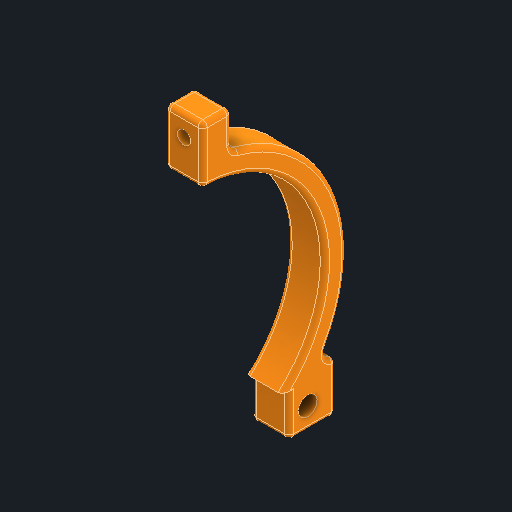
# Autodesk Inventor part: ra_wrap_strap_mz
Saved by Autodesk Inventor 2027.1 (Build 311270010, 270A)
## iProperties
Created: 2026-11-04
Part Number: ra_wrap_strap_mz
Material: Generic
Description: RA wrap strap -Z half: wraps over the RA body, lug on the flat bit -Z axial M5 (M5x25), M4x20 top joint into an M4 nut; print PETG/ASA
Document SubType Name: Modeling
Designer: Claude (from photos)
Density: 1 g/cm^3
Appearance: Orange
Mass: 11.5728 g
Surface Area: 53.282 cm^2
Volume: 11.5728 cm^3
Author: alexg
Autodesk Inventor part; units mm, degrees
ref_plane "Work Plane1" through (1, 0, 0) normal (1, 0, 0) x (0, 1, 0)
sketch "Band sketch" plane through (1, 0, 0) normal (1, 0, 0) x (0, 1, 0)
  circle A0 centre (0, 0) radius 47
  constraints: 1 centre point
extrude "Band" add sketch "Band sketch" along normal blind 12
ref_plane "Work Plane2" through (1, 0, 0) normal (1, 0, 0) x (0, 1, 0)
sketch "Keep this half sketch" plane through (1, 0, 0) normal (1, 0, 0) x (0, 1, 0)
  line L0 (-60, -0.75) -> (60, -0.75)
  line L1 (60, -0.75) -> (60, 60)
  line L2 (60, 60) -> (-60, 60)
  line L3 (-60, 60) -> (-60, -0.75)
  constraints: 8 end point, 2 parallel, 1 horizontal, 1 perpendicular
extrude "Keep this half" cut sketch "Keep this half sketch" along normal blind 12
ref_plane "Work Plane3" through (1, 0, 0) normal (1, 0, 0) x (0, 1, 0)
sketch "Open below the RA body (latitude pivot web) sketch" plane through (1, 0, 0) normal (1, 0, 0) x (0, 1, 0)
  line L0 (-60, -60) -> (-30, -60)
  line L1 (-30, -60) -> (-30, 60)
  line L2 (-30, 60) -> (-60, 60)
  line L3 (-60, 60) -> (-60, -60)
  constraints: 8 end point, 2 parallel, 1 horizontal, 1 perpendicular
extrude "Open below the RA body (latitude pivot web)" cut sketch "Open below the RA body (latitude pivot web) sketch" along normal blind 12
ref_plane "Work Plane4" through (1, 0, 0) normal (1, 0, 0) x (0, 1, 0)
sketch "Lug on the flat bit axial M5 sketch" plane through (1, 0, 0) normal (1, 0, 0) x (0, 1, 0)
  line L0 (-44, -43.5) -> (-28, -43.5)
  line L1 (-28, -43.5) -> (-28, -28.5)
  line L2 (-28, -28.5) -> (-44, -28.5)
  line L3 (-44, -28.5) -> (-44, -43.5)
  constraints: 8 end point, 2 parallel, 1 horizontal, 1 perpendicular
extrude "Lug on the flat bit axial M5" add sketch "Lug on the flat bit axial M5 sketch" along normal blind 12
ref_plane "Work Plane5" through (1, 0, 0) normal (1, 0, 0) x (0, 1, 0)
sketch "Top clamp ear sketch" plane through (1, 0, 0) normal (1, 0, 0) x (0, 1, 0)
  line L0 (42, -10) -> (58, -10)
  line L1 (58, -10) -> (58, -0.75)
  line L2 (58, -0.75) -> (42, -0.75)
  line L3 (42, -0.75) -> (42, -10)
  constraints: 8 end point, 2 parallel, 1 horizontal, 1 perpendicular
extrude "Top clamp ear" add sketch "Top clamp ear sketch" along normal blind 12
ref_plane "Work Plane6" through (1, 0, 0) normal (1, 0, 0) x (0, 1, 0)
sketch "RA body bore sketch" plane through (1, 0, 0) normal (1, 0, 0) x (0, 1, 0)
  circle A0 centre (0, 0) radius 40
  constraints: 1 centre point
extrude "RA body bore" cut sketch "RA body bore sketch" along normal blind 12
ref_plane "Work Plane7" through (1, 0, 0) normal (1, 0, 0) x (0, 1, 0)
sketch "M5 hole (6 mm) sketch" plane through (1, 0, 0) normal (1, 0, 0) x (0, 1, 0)
  circle A0 centre (-37, -34.5) radius 3
  constraints: 1 centre point
extrude "M5 hole (6 mm)" cut sketch "M5 hole (6 mm) sketch" along normal blind 12
sketch "M4 heat-set insert pocket (top joint) sketch" plane through (0, 0, 0) normal (0, 0, 1) x (1, 0, 0)
  circle A0 centre (7, 51.5) radius 2.1
  constraints: 1 centre point
extrude "M4 clearance (top joint, 4.2)" cut sketch "M4 heat-set insert pocket (top joint) sketch" against normal blind 10.5
fillet "Fillets (inside corners) R3 (2 edges)" radius 3 2 edges at (7, 45.9239, -10) (7, -28, -37.7492)
fillet "Rounds (outside edges) R1.5 (22 edges)" radius 1.5 22 edges at (13, 13.7907, -37.5475) (7, 39.993, -0.75) (1, 13.7907, -37.5475) (1, 48.9965, -0.75) (1, 58, -5.375) (1, 53.1402, -10) (1, 17.9596, -43.4333) (1, -36, -43.5) (1, -44, -36) (1, -37, -28.5) (13, 48.9965, -0.75) (7, 58, -0.75) (7, 58, -10) (13, 53.1402, -10) (13, 58, -5.375) (13, -37, -28.5) (13, -44, -36) (13, -36, -43.5) (13, 17.9596, -43.4333) (7, -28, -43.5) (7, -44, -43.5) (7, -44, -28.5)
ref_plane "Work Plane8" through (0, 0, -10) normal (0, 0, 1) x (1, 0, 0)
sketch "M4 nut pocket (top joint, 5.2 deep: M4x20 ends flush) sketch" plane through (0, 0, -10) normal (0, 0, 1) x (1, 0, 0)
  line L0 (7, 55.6569) -> (3.4, 53.5785)
  line L1 (3.4, 53.5785) -> (3.4, 49.4215)
  line L2 (3.4, 49.4215) -> (7, 47.3431)
  line L3 (7, 47.3431) -> (10.6, 49.4215)
  line L4 (10.6, 49.4215) -> (10.6, 53.5785)
  line L5 (10.6, 53.5785) -> (7, 55.6569)
  constraints: 12 end point
extrude "M4 nut pocket (top joint, 5.2 deep: M4x20 ends flush)" cut sketch "M4 nut pocket (top joint, 5.2 deep: M4x20 ends flush) sketch" along normal blind 5.2
body "Solid1"
